Autodesk Fusion 360 part; units mm, degrees
(part 3 of 8)
extrude "Clip Spokes to Octagon" cut sketch "Spoke Outer Envelope" along normal mid plane 260 keep common part bodies 3 in component "A Housing"
fillet "A Central Spoke Root Blends" radius 1 16 edges at (0.649, 12.786, 24.5428) (18.8873, -5.4523, 19.4883) (-5.4523, 18.8873, -19.4883) (23.038, -9.6029, -11.9702) (18.8873, -5.4523, -19.4883) (-11.5425, 24.9775, -3.024) (-9.6029, 23.038, -11.9702) (0.649, 12.786, -24.5428) (12.786, 0.649, -24.5428) (-11.5905, 25.0255, 2.3734) (25.0255, -11.5905, -2.3734) (25.0255, -11.5905, 2.3734) (23.038, -9.6029, 11.9702) (12.786, 0.649, 24.5428) (-5.4523, 18.8873, 19.4883) (-9.6029, 23.038, 11.9702) on bodies 3 in component "A Housing"
ref_plane "WorkPlane19" through (7.4953, 7.4953, 12.125) normal (0.707107, 0.707107, 0) x (0, 0, 1) in component "A Housing"
sketch "A Rear Carrier Clearance sketch" plane through (7.4953, 7.4953, 0) normal (0.707107, 0.707107, 0) x (0, 0, 1) in component "A Housing"
  circle A0 centre (0, 0) radius 23
  dimension "d690" = 46
  measures "d690" diameter of A0
extrude "A Rear Carrier Clearance" cut sketch "A Rear Carrier Clearance sketch" along normal blind 18 bodies 3 in component "A Housing"
ref_plane "WorkPlane20" through (0.3536, 0.3536, 12.125) normal (0.707107, 0.707107, 0) x (0, 0, 1) in component "A Housing"
sketch "A Seal Relief sketch" plane through (0.3536, 0.3536, 0) normal (0.707107, 0.707107, 0) x (0, 0, 1) in component "A Housing"
  circle A0 centre (0, 0) radius 9.75
  dimension "d695" = 19.5
  measures "d695" diameter of A0
extrude "A Seal Relief" cut sketch "A Seal Relief sketch" along normal blind 10.1 bodies 3 in component "A Housing"
ref_plane "WorkPlane21" through (0.3536, 0.3536, 12.125) normal (0.707107, 0.707107, 0) x (0, 0, 1) in component "A Housing"
sketch "A Front Bearing Seat sketch" plane through (0.3536, 0.3536, 0) normal (0.707107, 0.707107, 0) x (0, 0, 1) in component "A Housing"
  circle A0 centre (0, 0) radius 11.1
  dimension "d700" = 22.2
  measures "d700" diameter of A0
extrude "A Front Bearing Seat" cut sketch "A Front Bearing Seat sketch" along normal blind 7.1 bodies 3 in component "A Housing"
ref_plane "WorkPlane22" through (0.3536, 0.3536, 12.125) normal (0.707107, 0.707107, 0) x (0, 0, 1) in component "A Housing"
sketch "A Support Bolt seed" plane through (0.3536, 0.3536, 0) normal (0.707107, 0.707107, 0) x (0, 0, 1) in component "A Housing"
  line L0 (0, 0) -> (17, 0) construction
  circle A0 centre (17, 0) radius 1.65
  dimension "d705" = 17
  dimension "d706" = 3.3
  constraint horizontal L0
  measures "d705" distance of L0.start L0.end
  measures "d706" diameter of A0
extrude "A Support Bolt bore" cut sketch "A Support Bolt seed" along normal blind 10.1 bodies 3 in component "A Housing"
pattern_circular "A Support Bolt pattern" count 3 over 360 about axis through (0.3536, 0.3536, 0) along (0.707107, 0.707107, 0) of "A Support Bolt bore" in component "A Housing"
ref_plane "WorkPlane23" through (0.3536, 0.3536, 12.125) normal (0.707107, 0.707107, 0) x (0, 0, 1) in component "A Housing"
sketch "A Front Bearing Boss sketch" plane through (0.3536, 0.3536, 0) normal (0.707107, 0.707107, 0) x (0, 0, 1) in component "A Housing"
  circle A0 centre (0, 0) radius 22
  dimension "d713" = 44
  measures "d713" diameter of A0
chamfer "A Bearing Entry Chamfer" distance 0.4 angle 45 1 edges at (-2.4847, 3.1918, -10.3488) tangent chain off on bodies 3 in component "A Housing"
ref_plane "WorkPlane24" through (0, 0, 75) normal (0, 0, 1) x (1, 0, 0) in component "A Housing"
sketch "A Collar Driver Corridors" plane through (0, 0, 75) normal (0, 0, 1) x (1, 0, 0) in component "A Housing"
  circle A0 centre (6.7175, 15.9099) radius 3
  circle A1 centre (15.9099, 6.7175) radius 3
  dimension "d717" = 6.7175
  dimension "d718" = 15.9099
  dimension "d719" = 6
  dimension "d720" = 15.9099
  dimension "d721" = 6.7175
  dimension "d722" = 6
  measures "d717" horizontal distance of origin A0.centre
  measures "d718" vertical distance of origin A0.centre
  measures "d719" diameter of A0
  measures "d720" horizontal distance of origin A1.centre
  measures "d721" vertical distance of origin A1.centre
  measures "d722" diameter of A1
extrude "A Collar Service Channels" cut sketch "A Collar Driver Corridors" against normal blind 75 bodies 3 in component "A Housing"
ref_plane "WorkPlane17" through (-0.3536, -0.3536, 12.125) normal (0.707107, 0.707107, 0) x (0, 0, 1) in component "B Moving Body"
sketch "B Central Carrier sketch" plane through (-0.3536, -0.3536, 0) normal (0.707107, 0.707107, 0) x (0, 0, 1) in component "B Moving Body"
  circle A0 centre (0, 0) radius 38
  dimension "d727" = 76
  measures "d727" diameter of A0
extrude "B Central Carrier" add sketch "B Central Carrier sketch" against normal blind 22.5 separate body makes body 6 in component "B Moving Body"
ref_plane "WorkPlane18" through (-0.3536, -0.3536, 12.125) normal (0.707107, 0.707107, 0) x (0, 0, 1) in component "B Moving Body"
sketch "B Spoke 1 Profile" plane through (-0.3536, -0.3536, 0) normal (0.707107, 0.707107, 0) x (0, 0, 1) in component "B Moving Body"
  line L0 (-4.7984, -1.4054) -> (37.3643, -145.3579)
  line L1 (37.3643, -145.3579) -> (46.9611, -142.547)
  line L2 (46.9611, -142.547) -> (4.7984, 1.4054)
  line L3 (4.7984, 1.4054) -> (-4.7984, -1.4054)
  dimension "d732" = 4.7984
  dimension "d733" = 1.4054
  dimension "d734" = 37.3643
  dimension "d735" = 145.3579
  dimension "d736" = 46.9611
  dimension "d737" = 142.547
  dimension "d738" = 4.7984
  dimension "d739" = 1.4054
  measures "d732" horizontal distance of origin L0.start
  measures "d733" vertical distance of origin L0.start
  measures "d734" horizontal distance of origin L0.end
  measures "d735" vertical distance of origin L0.end
  measures "d736" horizontal distance of origin L1.end
  measures "d737" vertical distance of origin L1.end
  measures "d738" horizontal distance of origin L2.end
  measures "d739" vertical distance of origin L2.end
extrude "B Deep Spoke 1" add sketch "B Spoke 1 Profile" against normal blind 18 bodies 4 6 in component "B Moving Body"
sketch "B Spoke 2 Profile" plane through (-0.3536, -0.3536, 0) normal (0.707107, 0.707107, 0) x (0, 0, 1) in component "B Moving Body"
  line L0 (-2.5272, -4.3143) -> (126.9012, -80.1317)
  line L1 (126.9012, -80.1317) -> (131.9557, -71.5031)
  line L2 (131.9557, -71.5031) -> (2.5272, 4.3143)
  line L3 (2.5272, 4.3143) -> (-2.5272, -4.3143)
  dimension "d742" = 2.5272
  dimension "d743" = 4.3143
  dimension "d744" = 126.9012
  dimension "d745" = 80.1317
  dimension "d746" = 131.9557
  dimension "d747" = 71.5031
  dimension "d748" = 2.5272
  dimension "d749" = 4.3143
  measures "d742" horizontal distance of origin L0.start
  measures "d743" vertical distance of origin L0.start
  measures "d744" horizontal distance of origin L0.end
  measures "d745" vertical distance of origin L0.end
  measures "d746" horizontal distance of origin L1.end
  measures "d747" vertical distance of origin L1.end
  measures "d748" horizontal distance of origin L2.end
  measures "d749" vertical distance of origin L2.end
extrude "B Deep Spoke 2" add sketch "B Spoke 2 Profile" against normal blind 18 bodies 4 in component "B Moving Body"
sketch "B Spoke 3 Profile" plane through (-0.3536, -0.3536, 0) normal (0.707107, 0.707107, 0) x (0, 0, 1) in component "B Moving Body"
  line L0 (2.5272, -4.3143) -> (131.9557, 71.5031)
  line L1 (131.9557, 71.5031) -> (126.9012, 80.1317)
  line L2 (126.9012, 80.1317) -> (-2.5272, 4.3143)
  line L3 (-2.5272, 4.3143) -> (2.5272, -4.3143)
  dimension "d752" = 2.5272
  dimension "d753" = 4.3143
  dimension "d754" = 131.9557
  dimension "d755" = 71.5031
  dimension "d756" = 126.9012
  dimension "d757" = 80.1317
  dimension "d758" = 2.5272
  dimension "d759" = 4.3143
  measures "d752" horizontal distance of origin L0.start
  measures "d753" vertical distance of origin L0.start
  measures "d754" horizontal distance of origin L0.end
  measures "d755" vertical distance of origin L0.end
  measures "d756" horizontal distance of origin L1.end
  measures "d757" vertical distance of origin L1.end
  measures "d758" horizontal distance of origin L2.end
  measures "d759" vertical distance of origin L2.end
extrude "B Deep Spoke 3" add sketch "B Spoke 3 Profile" against normal blind 18 bodies 4 in component "B Moving Body"
sketch "B Spoke 4 Profile" plane through (-0.3536, -0.3536, 0) normal (0.707107, 0.707107, 0) x (0, 0, 1) in component "B Moving Body"
  line L0 (4.7984, -1.4054) -> (46.9611, 142.547)
  line L1 (46.9611, 142.547) -> (37.3643, 145.3579)
  line L2 (37.3643, 145.3579) -> (-4.7984, 1.4054)
  line L3 (-4.7984, 1.4054) -> (4.7984, -1.4054)
  dimension "d762" = 4.7984
  dimension "d763" = 1.4054
  dimension "d764" = 46.9611
  dimension "d765" = 142.547
  dimension "d766" = 37.3643
  dimension "d767" = 145.3579
  dimension "d768" = 4.7984
  dimension "d769" = 1.4054
  measures "d762" horizontal distance of origin L0.start
  measures "d763" vertical distance of origin L0.start
  measures "d764" horizontal distance of origin L0.end
  measures "d765" vertical distance of origin L0.end
  measures "d766" horizontal distance of origin L1.end
  measures "d767" vertical distance of origin L1.end
  measures "d768" horizontal distance of origin L2.end
  measures "d769" vertical distance of origin L2.end
extrude "B Deep Spoke 4" add sketch "B Spoke 4 Profile" against normal blind 18 bodies 4 in component "B Moving Body"
sketch "B Spoke 5 Profile" plane through (-0.3536, -0.3536, 0) normal (0.707107, 0.707107, 0) x (0, 0, 1) in component "B Moving Body"
  line L0 (4.7984, 1.4054) -> (-37.3643, 145.3579)
  line L1 (-37.3643, 145.3579) -> (-46.9611, 142.547)
  line L2 (-46.9611, 142.547) -> (-4.7984, -1.4054)
  line L3 (-4.7984, -1.4054) -> (4.7984, 1.4054)
  dimension "d772" = 4.7984
  dimension "d773" = 1.4054
  dimension "d774" = 37.3643
  dimension "d775" = 145.3579
  dimension "d776" = 46.9611
  dimension "d777" = 142.547
  dimension "d778" = 4.7984
  dimension "d779" = 1.4054
  measures "d772" horizontal distance of origin L0.start
  measures "d773" vertical distance of origin L0.start
  measures "d774" horizontal distance of origin L0.end
  measures "d775" vertical distance of origin L0.end
  measures "d776" horizontal distance of origin L1.end
  measures "d777" vertical distance of origin L1.end
  measures "d778" horizontal distance of origin L2.end
  measures "d779" vertical distance of origin L2.end
extrude "B Deep Spoke 5" add sketch "B Spoke 5 Profile" against normal blind 18 bodies 4 in component "B Moving Body"
sketch "B Spoke 6 Profile" plane through (-0.3536, -0.3536, 0) normal (0.707107, 0.707107, 0) x (0, 0, 1) in component "B Moving Body"
  line L0 (2.5272, 4.3143) -> (-126.9012, 80.1317)
  line L1 (-126.9012, 80.1317) -> (-131.9557, 71.5031)
  line L2 (-131.9557, 71.5031) -> (-2.5272, -4.3143)
  line L3 (-2.5272, -4.3143) -> (2.5272, 4.3143)
  dimension "d782" = 2.5272
  dimension "d783" = 4.3143
  dimension "d784" = 126.9012
  dimension "d785" = 80.1317
  dimension "d786" = 131.9557
  dimension "d787" = 71.5031
  dimension "d788" = 2.5272
  dimension "d789" = 4.3143
  measures "d782" horizontal distance of origin L0.start
  measures "d783" vertical distance of origin L0.start
  measures "d784" horizontal distance of origin L0.end
  measures "d785" vertical distance of origin L0.end
  measures "d786" horizontal distance of origin L1.end
  measures "d787" vertical distance of origin L1.end
  measures "d788" horizontal distance of origin L2.end
  measures "d789" vertical distance of origin L2.end
extrude "B Deep Spoke 6" add sketch "B Spoke 6 Profile" against normal blind 18 bodies 4 in component "B Moving Body"
sketch "B Spoke 7 Profile" plane through (-0.3536, -0.3536, 0) normal (0.707107, 0.707107, 0) x (0, 0, 1) in component "B Moving Body"
  line L0 (-2.5272, 4.3143) -> (-131.9557, -71.5031)
  line L1 (-131.9557, -71.5031) -> (-126.9012, -80.1317)
  line L2 (-126.9012, -80.1317) -> (2.5272, -4.3143)
  line L3 (2.5272, -4.3143) -> (-2.5272, 4.3143)
  dimension "d792" = 2.5272
  dimension "d793" = 4.3143
  dimension "d794" = 131.9557
  dimension "d795" = 71.5031
  dimension "d796" = 126.9012
  dimension "d797" = 80.1317
  dimension "d798" = 2.5272
  dimension "d799" = 4.3143
  measures "d792" horizontal distance of origin L0.start
  measures "d793" vertical distance of origin L0.start
  measures "d794" horizontal distance of origin L0.end
  measures "d795" vertical distance of origin L0.end
  measures "d796" horizontal distance of origin L1.end
  measures "d797" vertical distance of origin L1.end
  measures "d798" horizontal distance of origin L2.end
  measures "d799" vertical distance of origin L2.end
extrude "B Deep Spoke 7" add sketch "B Spoke 7 Profile" against normal blind 18 bodies 4 in component "B Moving Body"
sketch "B Spoke 8 Profile" plane through (-0.3536, -0.3536, 0) normal (0.707107, 0.707107, 0) x (0, 0, 1) in component "B Moving Body"
  line L0 (-4.7984, 1.4054) -> (-46.9611, -142.547)
  line L1 (-46.9611, -142.547) -> (-37.3643, -145.3579)
  line L2 (-37.3643, -145.3579) -> (4.7984, 1.4054)
  line L3 (4.7984, 1.4054) -> (-4.7984, 1.4054)
  dimension "d802" = 4.7984
  dimension "d803" = 1.4054
  dimension "d804" = 46.9611
  dimension "d805" = 142.547
  dimension "d806" = 37.3643
  dimension "d807" = 145.3579
  dimension "d808" = 4.7984
  dimension "d809" = 1.4054
  measures "d802" horizontal distance of origin L0.start
  measures "d803" vertical distance of origin L0.start
  measures "d804" horizontal distance of origin L0.end
  measures "d805" vertical distance of origin L0.end
  measures "d806" horizontal distance of origin L1.end
  measures "d807" vertical distance of origin L1.end
  measures "d808" horizontal distance of origin L2.end
  measures "d809" vertical distance of origin L2.end
extrude "B Deep Spoke 8" add sketch "B Spoke 8 Profile" against normal blind 18 bodies 4 in component "B Moving Body"
sketch "Spoke Outer Envelope (2)" plane through (0, 0, 0) normal (1, 0, 0) x (0, 0, -1) in component "B Moving Body"
  line L0 (75, 31.066) -> (31.066, 75)
  line L1 (31.066, 75) -> (-31.066, 75)
  line L2 (-31.066, 75) -> (-75, 31.066)
  line L3 (-75, 31.066) -> (-75, -31.066)
  line L4 (-75, -31.066) -> (-31.066, -75)
  line L5 (-31.066, -75) -> (31.066, -75)
  line L6 (31.066, -75) -> (75, -31.066)
  line L7 (75, -31.066) -> (75, 31.066)
  dimension "d812" = 150
  constraint horizontal L1
  measures "d812" vertical distance of L0.end L5.end
extrude "Clip Spokes to Octagon'" cut sketch "Spoke Outer Envelope (2)" along normal mid plane 260 keep common part bodies 4 in component "B Moving Body"
fillet "B Central Spoke Root Blends" radius 1 16 edges at (-31.2863, 17.8512, 15.3868) (3.6952, -17.1302, 35.0307) (-23.2315, 9.7965, 29.9762) (19.8388, -33.2738, -5.7899) (-23.2315, 9.7965, -29.9762) (-33.2076, 19.7726, -6.3678) (-31.2863, 17.8512, -15.3868) (-17.1302, 3.6952, -35.0307) (3.6952, -17.1302, -35.0307) (9.7965, -23.2315, -29.9762) (17.8512, -31.2863, -15.3868) (19.8388, -33.2738, 5.7899) (17.8512, -31.2863, 15.3868) (9.7965, -23.2315, 29.9762) (-17.1302, 3.6952, 35.0307) (-33.2738, 19.8388, 5.7899) on bodies 4 in component "B Moving Body"
ref_plane "WorkPlane19" through (-0.3536, -0.3536, 12.125) normal (0.707107, 0.707107, 0) x (0, 0, 1) in component "B Moving Body"
sketch "B Open Hub Cavity sketch" plane through (-0.3536, -0.3536, 0) normal (0.707107, 0.707107, 0) x (0, 0, 1) in component "B Moving Body"
  circle A0 centre (0, 0) radius 25.15
  dimension "d819" = 50.3
  measures "d819" diameter of A0
extrude "B Open Hub Cavity" cut sketch "B Open Hub Cavity sketch" against normal blind 22.5 bodies 4 in component "B Moving Body"
ref_plane "WorkPlane20" through (-0.3536, -0.3536, 12.125) normal (0.707107, 0.707107, 0) x (0, 0, 1) in component "B Moving Body"
sketch "B Four Mount Holes" plane through (-0.3536, -0.3536, 0) normal (0.707107, 0.707107, 0) x (0, 0, 1) in component "B Moving Body"
  circle A0 centre (22.6274, 22.6274) radius 2.15
  circle A1 centre (-22.6274, 22.6274) radius 2.15
  circle A2 centre (-22.6274, -22.6274) radius 2.15
  circle A3 centre (22.6274, -22.6274) radius 2.15
  dimension "d824" = 22.6274
  dimension "d825" = 22.6274
  dimension "d826" = 4.3
  dimension "d827" = 22.6274
  dimension "d828" = 22.6274
  dimension "d829" = 4.3
  dimension "d830" = 22.6274
  dimension "d831" = 22.6274
  dimension "d832" = 4.3
  dimension "d833" = 22.6274
  dimension "d834" = 22.6274
  dimension "d835" = 4.3
  measures "d824" horizontal distance of origin A0.centre
  measures "d825" vertical distance of origin A0.centre
  measures "d826" diameter of A0
  measures "d827" horizontal distance of origin A1.centre
  measures "d828" vertical distance of origin A1.centre
  measures "d829" diameter of A1
  measures "d830" horizontal distance of origin A2.centre
  measures "d831" vertical distance of origin A2.centre
  measures "d832" diameter of A2
  measures "d833" horizontal distance of origin A3.centre
  measures "d834" vertical distance of origin A3.centre
  measures "d835" diameter of A3
extrude "B M4 Through Holes" cut sketch "B Four Mount Holes" against normal blind 22.5 bodies 4 in component "B Moving Body"
sketch "B M4 Nut Pocket 1" plane through (-0.3536, -0.3536, 0) normal (0.707107, 0.707107, 0) x (0, 0, 1) in component "B Moving Body"
  circle A0 centre (22.6274, 22.6274) radius 4.1569 construction
  line L0 (26.7843, 22.6274) -> (24.7059, 26.2274)
  line L1 (24.7059, 26.2274) -> (20.549, 26.2274)
  line L2 (20.549, 26.2274) -> (18.4705, 22.6274)
  line L3 (18.4705, 22.6274) -> (20.549, 19.0274)
  line L4 (20.549, 19.0274) -> (24.7059, 19.0274)
  line L5 (24.7059, 19.0274) -> (26.7843, 22.6274)
  dimension "d838" = 22.6274
  dimension "d839" = 22.6274
  dimension "d840" = 8.3138
  constraint coincident A0 L0.start
  constraint coincident A0 L0.end
  constraint coincident A0 L1.end
  constraint coincident A0 L2.end
  constraint coincident A0 L3.end
  constraint coincident A0 L4.end
  constraint equal L0 L1
  constraint equal L0 L2
  constraint equal L0 L3
  constraint equal L0 L4
  constraint equal L0 L5
  constraint horizontal L1
  measures "d838" horizontal distance of origin A0.centre
  measures "d839" vertical distance of origin A0.centre
  measures "d840" diameter of A0
extrude "B Open M4 Nut Trap 1" cut sketch "B M4 Nut Pocket 1" against normal blind 4 bodies 4 in component "B Moving Body"
sketch "B M4 Nut Pocket 2" plane through (-0.3536, -0.3536, 0) normal (0.707107, 0.707107, 0) x (0, 0, 1) in component "B Moving Body"
  circle A0 centre (-22.6274, 22.6274) radius 4.1569 construction
  line L0 (-18.4705, 22.6274) -> (-20.549, 26.2274)
  line L1 (-20.549, 26.2274) -> (-24.7059, 26.2274)
  line L2 (-24.7059, 26.2274) -> (-26.7843, 22.6274)
  line L3 (-26.7843, 22.6274) -> (-24.7059, 19.0274)
  line L4 (-24.7059, 19.0274) -> (-20.549, 19.0274)
  line L5 (-20.549, 19.0274) -> (-18.4705, 22.6274)
  dimension "d843" = 22.6274
  dimension "d844" = 22.6274
  dimension "d845" = 8.3138
  constraint coincident A0 L0.start
  constraint coincident A0 L0.end
  constraint coincident A0 L1.end
  constraint coincident A0 L2.end
  constraint coincident A0 L3.end
  constraint coincident A0 L4.end
  constraint equal L0 L1
  constraint equal L0 L2
  constraint equal L0 L3
  constraint equal L0 L4
  constraint equal L0 L5
  constraint horizontal L1
  measures "d843" horizontal distance of origin A0.centre
  measures "d844" vertical distance of origin A0.centre
  measures "d845" diameter of A0
extrude "B Open M4 Nut Trap 2" cut sketch "B M4 Nut Pocket 2" against normal blind 4 bodies 4 in component "B Moving Body"
sketch "B M4 Nut Pocket 3" plane through (-0.3536, -0.3536, 0) normal (0.707107, 0.707107, 0) x (0, 0, 1) in component "B Moving Body"
  circle A0 centre (-22.6274, -22.6274) radius 4.1569 construction
  line L0 (-18.4705, -22.6274) -> (-20.549, -19.0274)
  line L1 (-20.549, -19.0274) -> (-24.7059, -19.0274)
  line L2 (-24.7059, -19.0274) -> (-26.7843, -22.6274)
  line L3 (-26.7843, -22.6274) -> (-24.7059, -26.2274)
  line L4 (-24.7059, -26.2274) -> (-20.549, -26.2274)
  line L5 (-20.549, -26.2274) -> (-18.4705, -22.6274)
  dimension "d848" = 22.6274
  dimension "d849" = 22.6274
  dimension "d850" = 8.3138
  constraint coincident A0 L0.start
  constraint coincident A0 L0.end
  constraint coincident A0 L1.end
  constraint coincident A0 L2.end
  constraint coincident A0 L3.end
  constraint coincident A0 L4.end
  constraint equal L0 L1
  constraint equal L0 L2
  constraint equal L0 L3
  constraint equal L0 L4
  constraint equal L0 L5
  constraint horizontal L1
  measures "d848" horizontal distance of origin A0.centre
  measures "d849" vertical distance of origin A0.centre
  measures "d850" diameter of A0
extrude "B Open M4 Nut Trap 3" cut sketch "B M4 Nut Pocket 3" against normal blind 4 bodies 4 in component "B Moving Body"
sketch "B M4 Nut Pocket 4" plane through (-0.3536, -0.3536, 0) normal (0.707107, 0.707107, 0) x (0, 0, 1) in component "B Moving Body"
  circle A0 centre (22.6274, -22.6274) radius 4.1569 construction
  line L0 (26.7843, -22.6274) -> (24.7059, -19.0274)
  line L1 (24.7059, -19.0274) -> (20.549, -19.0274)
  line L2 (20.549, -19.0274) -> (18.4705, -22.6274)
  line L3 (18.4705, -22.6274) -> (20.549, -26.2274)
  line L4 (20.549, -26.2274) -> (24.7059, -26.2274)
  line L5 (24.7059, -26.2274) -> (26.7843, -22.6274)
  dimension "d853" = 22.6274
  dimension "d854" = 22.6274
  dimension "d855" = 8.3138
  constraint coincident A0 L0.start
  constraint coincident A0 L0.end
  constraint coincident A0 L1.end
  constraint coincident A0 L2.end
  constraint coincident A0 L3.end
  constraint coincident A0 L4.end
  constraint equal L0 L1
  constraint equal L0 L2
  constraint equal L0 L3
  constraint equal L0 L4
  constraint equal L0 L5
  constraint horizontal L1
  measures "d853" horizontal distance of origin A0.centre
  measures "d854" vertical distance of origin A0.centre
  measures "d855" diameter of A0
extrude "B Open M4 Nut Trap 4" cut sketch "B M4 Nut Pocket 4" against normal blind 4 bodies 4 in component "B Moving Body"
sketch "B Hub Service Slots" plane through (0, 0, 0) normal (0, 0, 1) x (1, 0, 0) in component "B Moving Body"
  line L0 (-14.8492, 3.5355) -> (-30.4056, -12.0208)
  line L1 (-30.4056, -12.0208) -> (-12.0208, -30.4056)
  line L2 (-12.0208, -30.4056) -> (3.5355, -14.8492)
  line L3 (3.5355, -14.8492) -> (-14.8492, 3.5355)
  dimension "d858" = 14.8492
  dimension "d859" = 3.5355
  dimension "d860" = 30.4056
  dimension "d861" = 12.0208
  dimension "d862" = 12.0208
  dimension "d863" = 30.4056
  dimension "d864" = 3.5355
  dimension "d865" = 14.8492
  measures "d858" horizontal distance of origin L0.start
  measures "d859" vertical distance of origin L0.start
  measures "d860" horizontal distance of origin L0.end
  measures "d861" vertical distance of origin L0.end
  measures "d862" horizontal distance of origin L1.end
  measures "d863" vertical distance of origin L1.end
  measures "d864" horizontal distance of origin L2.end
  measures "d865" vertical distance of origin L2.end
extrude "B Hub Side Access" cut sketch "B Hub Service Slots" along normal mid plane 76 bodies 4 in component "B Moving Body"
chamfer "A Outer Joint Bed Edge Relief" distance 0.3 angle 45 8 edges at (-74.2929, 75, 0) (-52.3259, 53.033, -53.033) (0.7071, 0, -75) (53.7401, -53.033, -53.033) (75.7071, -75, 0) (53.7401, -53.033, 53.033) (0.7071, 0, 75) (-52.3259, 53.033, 53.033) tangent chain off on bodies 3 in component "A Housing"
chamfer "A Outside Corner Bevels" distance 0.5 angle 45 8 edges at (103.0373, -75, 31.066) (81.0987, -31.066, 75) (103.0373, -75, -31.066) (81.0987, -31.066, -75) (50.0327, 31.066, -75) (28.0373, 75, 31.066) (28.0373, 75, -31.066) (50.0327, 31.066, 75) tangent chain off on bodies 3 in component "A Housing"
chamfer "A Open End Rim Relief" distance 0.3 angle 45 24 edges at (130, 30.9928, 74.8232) (130, 53.033, 53.033) (130, 49.851, 49.851) (130, 70.5, 0) (130, 49.851, -49.851) (130, 0, -70.5) (130, -49.851, -49.851) (130, -70.5, 0) (130, -49.851, 49.851) (130, 0, 70.5) (130, 0, 75) (130, -30.9928, 74.8232) (130, -53.033, 53.033) (130, -74.8232, 30.9928) (130, -75, 0) (130, -74.8232, -30.9928) (130, -53.033, -53.033) (130, -30.9928, -74.8232) (130, 0, -75) (130, 30.9928, -74.8232) (130, 53.033, -53.033) (130, 74.8232, -30.9928) (130, 75, 0) (130, 74.8232, 30.9928) tangent chain off on bodies 3 in component "A Housing"
ref_plane "WorkPlane25" through (12.125, 0, 0) normal (0, 0, 1) x (1, 0, 0) in component "A Housing"
ref_plane "WorkPlane26" through (12.125, 0, 75) normal (0, 0, 1) x (1, 0, 0) in component "A Housing"
sketch "A End Cord Port" plane through (0, 0, 75) normal (0, 0, 1) x (1, 0, 0) in component "A Housing"
  circle A0 centre (125, 0) radius 2.25
  line L0 (0, 0) -> (125, 0) construction
  dimension "d875" = 125
  dimension "d876" = 4.5
  constraint horizontal L0
  measures "d875" distance of L0.start A0.centre
  measures "d876" diameter of A0
extrude "A Cord Port 90" cut sketch "A End Cord Port" against normal blind 4.5 bodies 3 in component "A Housing"
chamfer "A Cord Port Lead Ins 90" distance 0.3 angle 45 2 edges at (122.9023, -0.8136, 70.5) (122.9023, 0.8136, 75) tangent chain off on bodies 3 in component "A Housing"
ref_plane "WorkPlane27" through (12.125, 0, 0) normal (0, 0, -1) x (1, 0, 0) in component "A Housing"
ref_plane "WorkPlane28" through (12.125, 0, -75) normal (0, 0, -1) x (1, 0, 0) in component "A Housing"
sketch "A End Cord Port (1)" plane through (0, 0, -75) normal (0, 0, -1) x (-1, 0, 0) in component "A Housing"
  circle A0 centre (-125, 0) radius 2.25
  line L0 (0, 0) -> (-125, 0) construction
  dimension "d884" = 125
  dimension "d885" = 4.5
  constraint horizontal L0
  measures "d884" distance of L0.start A0.centre
  measures "d885" diameter of A0
extrude "A Cord Port 270" cut sketch "A End Cord Port (1)" against normal blind 4.5 bodies 3 in component "A Housing"
chamfer "A Cord Port Lead Ins 270" distance 0.3 angle 45 2 edges at (127.0977, -0.8136, -70.5) (127.0977, 0.8136, -75) tangent chain off on bodies 3 in component "A Housing"
chamfer "B Outer Joint Bed Edge Relief" distance 0.3 angle 45 8 edges at (-0.7071, 0, 75) (52.3259, -53.033, 53.033) (74.2929, -75, 0) (52.3259, -53.033, -53.033) (-0.7071, 0, -75) (-53.7401, 53.033, -53.033) (-75.7071, 75, 0) (-53.7401, 53.033, 53.033) tangent chain off on bodies 4 in component "B Moving Body"
chamfer "B Outside Corner Bevels" distance 0.5 angle 45 8 edges at (-28.0373, -75, 31.066) (-28.0373, -75, -31.066) (-50.0327, -31.066, 75) (-81.0987, 31.066, 75) (-103.0373, 75, 31.066) (-103.0373, 75, -31.066) (-81.0987, 31.066, -75) (-50.0327, -31.066, -75) tangent chain off on bodies 4 in component "B Moving Body"
chamfer "B Open End Rim Relief" distance 0.3 angle 45 24 edges at (-130, -30.9928, -74.8232) (-130, 0, -75) (-130, 30.9928, -74.8232) (-130, 74.8232, -30.9928) (-130, 75, 0) (-130, -53.033, -53.033) (-130, -74.8232, -30.9928) (-130, -75, 0) (-130, -74.8232, 30.9928) (-130, -53.033, 53.033) (-130, -30.9928, 74.8232) (-130, 0, 75) (-130, 30.9928, 74.8232) (-130, 53.033, 53.033) (-130, 74.8232, 30.9928) (-130, 53.033, -53.033) (-130, 49.851, 49.851) (-130, 0, 70.5) (-130, -49.851, 49.851) (-130, -70.5, 0) (-130, -49.851, -49.851) (-130, 0, -70.5) (-130, 49.851, -49.851) (-130, 70.5, 0) tangent chain off on bodies 4 in component "B Moving Body"
ref_plane "WorkPlane21" through (12.125, 0, 0) normal (0, 0, 1) x (1, 0, 0) in component "B Moving Body"
ref_plane "WorkPlane22" through (12.125, 0, 75) normal (0, 0, 1) x (1, 0, 0) in component "B Moving Body"
sketch "B End Cord Port" plane through (0, 0, 75) normal (0, 0, 1) x (1, 0, 0) in component "B Moving Body"
  circle A0 centre (-125, 0) radius 2.25
  line L0 (0, 0) -> (-125, 0) construction
  dimension "d896" = 125
  dimension "d897" = 4.5
  constraint horizontal L0
  measures "d896" distance of L0.start A0.centre
  measures "d897" diameter of A0
extrude "B Cord Port 90" cut sketch "B End Cord Port" against normal blind 4.5 bodies 4 in component "B Moving Body"
chamfer "B Cord Port Lead Ins 90" distance 0.3 angle 45 2 edges at (-127.0977, -0.8136, 70.5) (-127.0977, 0.8136, 75) tangent chain off on bodies 4 in component "B Moving Body"
ref_plane "WorkPlane23" through (12.125, 0, 0) normal (0, 0, -1) x (1, 0, 0) in component "B Moving Body"
ref_plane "WorkPlane24" through (12.125, 0, -75) normal (0, 0, -1) x (1, 0, 0) in component "B Moving Body"
sketch "B End Cord Port (1)" plane through (0, 0, -75) normal (0, 0, -1) x (-1, 0, 0) in component "B Moving Body"
  circle A0 centre (125, 0) radius 2.25
  line L0 (0, 0) -> (125, 0) construction
  dimension "d905" = 125
  dimension "d906" = 4.5
  constraint horizontal L0
  measures "d905" distance of L0.start A0.centre
  measures "d906" diameter of A0
extrude "B Cord Port 270" cut sketch "B End Cord Port (1)" against normal blind 4.5 bodies 4 in component "B Moving Body"
chamfer "B Cord Port Lead Ins 270" distance 0.3 angle 45 2 edges at (-122.9023, -0.8136, -70.5) (-122.9023, 0.8136, -75) tangent chain off on bodies 4 in component "B Moving Body"
ref_plane "WorkPlane1" through (15.9806, 15.9806, 12.125) normal (0.707107, 0.707107, 0) x (0, 0, 1) in component "D Rear Bearing Holder"
sketch "D Rear Holder Blank sketch" plane through (15.9806, 15.9806, 0) normal (0.707107, 0.707107, 0) x (0, 0, 1) in component "D Rear Bearing Holder"
  circle A0 centre (0, 0) radius 22
  dimension "d912" = 44
  measures "d912" diameter of A0
extrude "D Rear Holder Blank" add sketch "D Rear Holder Blank sketch" along normal blind 10.2 separate body makes body 7 in component "D Rear Bearing Holder"
ref_plane "WorkPlane2" through (15.9806, 15.9806, 12.125) normal (0.707107, 0.707107, 0) x (0, 0, 1) in component "D Rear Bearing Holder"
sketch "D Seal Relief sketch" plane through (15.9806, 15.9806, 0) normal (0.707107, 0.707107, 0) x (0, 0, 1) in component "D Rear Bearing Holder"
  circle A0 centre (0, 0) radius 9.75
  dimension "d917" = 19.5
  measures "d917" diameter of A0
extrude "D Seal Relief" cut sketch "D Seal Relief sketch" along normal blind 10.2 bodies 7 in component "D Rear Bearing Holder"
ref_plane "WorkPlane3" through (18.1019, 18.1019, 12.125) normal (0.707107, 0.707107, 0) x (0, 0, 1) in component "D Rear Bearing Holder"
sketch "D Rear Bearing Seat sketch" plane through (18.1019, 18.1019, 0) normal (0.707107, 0.707107, 0) x (0, 0, 1) in component "D Rear Bearing Holder"
  circle A0 centre (0, 0) radius 11.1
  dimension "d922" = 22.2
  measures "d922" diameter of A0
extrude "D Rear Bearing Seat" cut sketch "D Rear Bearing Seat sketch" along normal blind 7.2 bodies 7 in component "D Rear Bearing Holder"
ref_plane "WorkPlane4" through (15.9806, 15.9806, 12.125) normal (0.707107, 0.707107, 0) x (0, 0, 1) in component "D Rear Bearing Holder"
sketch "D Support Bolt seed" plane through (15.9806, 15.9806, 0) normal (0.707107, 0.707107, 0) x (0, 0, 1) in component "D Rear Bearing Holder"
  line L0 (0, 0) -> (17, 0) construction
  circle A0 centre (17, 0) radius 1.65
  dimension "d927" = 17
  dimension "d928" = 3.3
  constraint horizontal L0
  measures "d927" distance of L0.start L0.end
  measures "d928" diameter of A0
extrude "D Support Bolt bore" cut sketch "D Support Bolt seed" along normal blind 10.2 bodies 7 in component "D Rear Bearing Holder"
pattern_circular "D Support Bolt pattern" count 3 over 360 about axis through (15.9806, 15.9806, 0) along (0.707107, 0.707107, 0) of "D Support Bolt bore" in component "D Rear Bearing Holder"
chamfer "D Bearing Entry Chamfer" distance 0.4 angle 45 1 edges at (26.0314, 20.3548, -10.3488) tangent chain off on bodies 7 in component "D Rear Bearing Holder"
chamfer "D Bed Edge Relief" distance 0.3 angle 45 1 edges at (10.3552, 21.606, -20.5112) tangent chain off on bodies 7 in component "D Rear Bearing Holder"
ref_plane "WorkPlane1" through (-1.7678, -1.7678, 12.125) normal (0.707107, 0.707107, 0) x (0, 0, 1) in component "C Front Bearing Cap"
sketch "C Front Bearing Cap Ring sketch" plane through (-1.7678, -1.7678, 0) normal (0.707107, 0.707107, 0) x (0, 0, 1) in component "C Front Bearing Cap"
  circle A0 centre (0, 0) radius 22
  circle A1 centre (0, 0) radius 9.75
  dimension "d937" = 44
  dimension "d938" = 19.5
  measures "d937" diameter of A0
  measures "d938" diameter of A1
extrude "C Front Bearing Cap Ring" add sketch "C Front Bearing Cap Ring sketch" along normal blind 3 separate body makes body 8 in component "C Front Bearing Cap"
ref_plane "WorkPlane2" through (-1.7678, -1.7678, 12.125) normal (0.707107, 0.707107, 0) x (0, 0, 1) in component "C Front Bearing Cap"
sketch "C Front Bearing Cap Bolt seed" plane through (-1.7678, -1.7678, 0) normal (0.707107, 0.707107, 0) x (0, 0, 1) in component "C Front Bearing Cap"
  line L0 (0, 0) -> (17, 0) construction
  circle A0 centre (17, 0) radius 1.65
  dimension "d943" = 17
  dimension "d944" = 3.3
  constraint horizontal L0
  measures "d943" distance of L0.start L0.end
  measures "d944" diameter of A0
extrude "C Front Bearing Cap Bolt bore" cut sketch "C Front Bearing Cap Bolt seed" along normal blind 3 bodies 8 in component "C Front Bearing Cap"
pattern_circular "C Front Bearing Cap Bolt pattern" count 3 over 360 about axis through (-1.7678, -1.7678, 0) along (0.707107, 0.707107, 0) of "C Front Bearing Cap Bolt bore" in component "C Front Bearing Cap"
chamfer "C Front Bearing Cap Outer Bed Relief" distance 0.3 angle 45 1 edges at (-7.3932, 3.8576, -20.5112) tangent chain off on bodies 8 in component "C Front Bearing Cap"
ref_plane "WorkPlane1" through (23.1931, 23.1931, 12.125) normal (0.707107, 0.707107, 0) x (0, 0, 1) in component "E Rear Bearing Cap"
sketch "E Rear Bearing Cap Ring sketch" plane through (23.1931, 23.1931, 0) normal (0.707107, 0.707107, 0) x (0, 0, 1) in component "E Rear Bearing Cap"
  circle A0 centre (0, 0) radius 22
  circle A1 centre (0, 0) radius 9.75
  dimension "d952" = 44
  dimension "d953" = 19.5
  measures "d952" diameter of A0
  measures "d953" diameter of A1
extrude "E Rear Bearing Cap Ring" add sketch "E Rear Bearing Cap Ring sketch" along normal blind 3 separate body makes body 9 in component "E Rear Bearing Cap"
ref_plane "WorkPlane2" through (23.1931, 23.1931, 12.125) normal (0.707107, 0.707107, 0) x (0, 0, 1) in component "E Rear Bearing Cap"
sketch "E Rear Bearing Cap Bolt seed" plane through (23.1931, 23.1931, 0) normal (0.707107, 0.707107, 0) x (0, 0, 1) in component "E Rear Bearing Cap"
  line L0 (0, 0) -> (17, 0) construction
  circle A0 centre (17, 0) radius 1.65
  dimension "d958" = 17
  dimension "d959" = 3.3
  constraint horizontal L0
  measures "d958" distance of L0.start L0.end
  measures "d959" diameter of A0
extrude "E Rear Bearing Cap Bolt bore" cut sketch "E Rear Bearing Cap Bolt seed" along normal blind 3 bodies 9 in component "E Rear Bearing Cap"
pattern_circular "E Rear Bearing Cap Bolt pattern" count 3 over 360 about axis through (23.1931, 23.1931, 0) along (0.707107, 0.707107, 0) of "E Rear Bearing Cap Bolt bore" in component "E Rear Bearing Cap"
chamfer "E Rear Bearing Cap Outer Bed Relief" distance 0.3 angle 45 1 edges at (17.5677, 28.8185, -20.5112) tangent chain off on bodies 9 in component "E Rear Bearing Cap"
ref_plane "WorkPlane1" through (-20.5061, -20.5061, 12.125) normal (0.707107, 0.707107, 0) x (0, 0, 1) in component "F Metal Hub Adapter"
sketch "F Adapter Flange sketch" plane through (-20.5061, -20.5061, 0) normal (0.707107, 0.707107, 0) x (0, 0, 1) in component "F Metal Hub Adapter"
  circle A0 centre (0, 0) radius 38
  dimension "d967" = 76
  measures "d967" diameter of A0
extrude "F Adapter Flange" add sketch "F Adapter Flange sketch" along normal blind 6 separate body makes body 10 in component "F Metal Hub Adapter"
ref_plane "WorkPlane2" through (-16.2635, -16.2635, 12.125) normal (0.707107, 0.707107, 0) x (0, 0, 1) in component "F Metal Hub Adapter"
sketch "F Centering Pilot sketch" plane through (-16.2635, -16.2635, 0) normal (0.707107, 0.707107, 0) x (0, 0, 1) in component "F Metal Hub Adapter"
  circle A0 centre (0, 0) radius 25
  circle A1 centre (0, 0) radius 17
  dimension "d972" = 50
  dimension "d973" = 34
  measures "d972" diameter of A0
  measures "d973" diameter of A1
extrude "F Centering Pilot" add sketch "F Centering Pilot sketch" along normal blind 2 bodies 10 in component "F Metal Hub Adapter"
ref_plane "WorkPlane3" through (-20.5061, -20.5061, 12.125) normal (0.707107, 0.707107, 0) x (0, 0, 1) in component "F Metal Hub Adapter"
sketch "F Shaft Clearance sketch" plane through (-20.5061, -20.5061, 0) normal (0.707107, 0.707107, 0) x (0, 0, 1) in component "F Metal Hub Adapter"
  circle A0 centre (0, 0) radius 4.25
  dimension "d978" = 8.5
  measures "d978" diameter of A0
extrude "F Shaft Clearance" cut sketch "F Shaft Clearance sketch" along normal blind 6 bodies 10 in component "F Metal Hub Adapter"
ref_plane "WorkPlane4" through (-20.5061, -20.5061, 12.125) normal (0.707107, 0.707107, 0) x (0, 0, 1) in component "F Metal Hub Adapter"